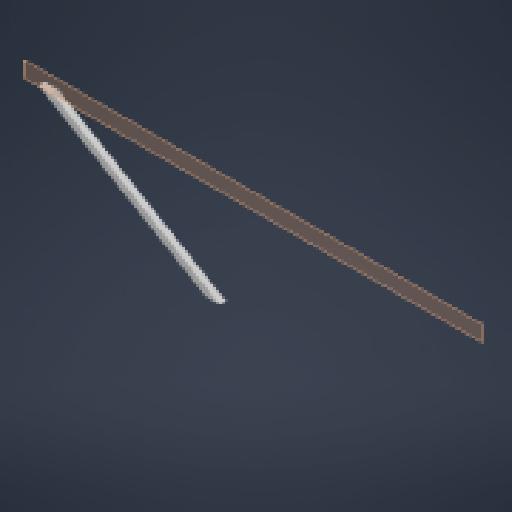
# Autodesk Inventor part: Bottom side diagonals
Saved by Autodesk Inventor 2027 (Build 310192000, 192)
## iProperties
Created: 2026-10-18
Part Number: Bottom side diagonals
Material: Generic
Document SubType Name: Modeling
Designer: lucas
Density: 1 g/cm^3
Appearance: Default
Author: lucas
Autodesk Inventor part; units mm, degrees
ref_plane "YZ Plane" through (0, 0, 0) normal (1, 0, 0) x (0, 1, 0)
ref_plane "XZ Plane" through (0, 0, 0) normal (0, 1, 0) x (-1, 0, 0)
ref_plane "XY Plane" through (0, 0, 0) normal (0, 0, 1) x (1, 0, 0)
ref_plane "Work Plane1" through (0, 0, 0) normal (0, 0, 1) x (1, 0, 0)
sketch "Sketch1" plane through (0, 0, 0) normal (0, 0, 1) x (1, 0, 0)
  line L0 (-203.2, -654.05) -> (-292.1, -654.05)
  line L1 (-292.1, -654.05) -> (-1320.8, -44.45)
  line L2 (-292.1, -602.7236) -> (-203.2, -654.05)
  line L3 (-292.1, -602.7236) -> (-1184.4498, -73.9237)
  line L4 (-1320.8, -44.45) -> (-1234.1866, -44.45)
  line L5 (-1234.1866, -44.45) -> (-1184.4498, -73.9237)
  point P0 (0, 0)
  constraints: 12 end point, 2 horizontal, 2 parallel, 3 other
extrude "Extrusion1" add sketch "Sketch1" against normal blind 38.1
body "Solid1"
